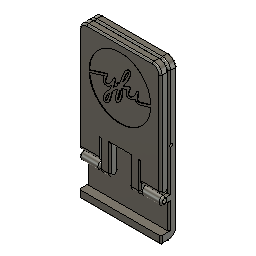
YFU Klap-Handy-Ständer (Autodesk Fusion 360 design; units mm, degrees)
Autodesk Fusion 360 part; units mm, degrees
sketch "Skizze1" plane through (0, 0, 0) normal (0, 0, 1) x (1, 0, 0)
  line L0 (25, -50) -> (-25, -50) construction
  line L1 (-25, -50) -> (-25, 45)
  line L2 (-20, 50) -> (20, 50)
  line L3 (25, 45) -> (25, -50)
  line L4 (25, -50) -> (-25, 50) construction
  line L5 (-25, -50) -> (25, 50) construction
  arc A0 (-20, 50) -> (-25, 45) centre (-20, 45) ccw
  arc A1 (25, 45) -> (20, 50) centre (20, 45) ccw
  line L6 (25, -45) -> (-25, -45)
  line L7 (25, -25) -> (-25, -25)
  line L8 (25, -20) -> (-25, -20)
  line L9 (-25, 50) -> (25, 0) construction
  line L10 (12.5, 7.5) -> (-12.5, 7.5) construction
  line L11 (-12.5, 7.5) -> (-12.5, 40.5)
  line L12 (-10.5, 42.5) -> (10.5, 42.5)
  line L13 (12.5, 40.5) -> (12.5, 7.5)
  line L14 (12.5, 7.5) -> (-12.5, 42.5) construction
  line L15 (-12.5, 7.5) -> (12.5, 42.5) construction
  line L16 (-12.5, 32.5) -> (12.5, 32.5)
  line L17 (-25, -20) -> (25, -25) construction
  line L18 (12.5, -25) -> (-12.5, -25)
  line L19 (-12.5, -25) -> (-12.5, -20)
  line L20 (-12.5, -20) -> (12.5, -20)
  line L21 (12.5, -20) -> (12.5, -25)
  line L22 (12.5, -25) -> (-12.5, -20) construction
  line L23 (-12.5, -25) -> (12.5, -20) construction
  arc A2 (-10.5, 42.5) -> (-12.5, 40.5) centre (-10.5, 40.5) ccw
  arc A3 (12.5, 40.5) -> (10.5, 42.5) centre (10.5, 40.5) ccw
  line L24 (25, -40) -> (-25, -40)
  line L25 (12.5, 7.5) -> (-12.5, 7.5) construction
  line L26 (-12.5, 7.5) -> (-12.5, 2.5)
  line L27 (-12.5, 2.5) -> (12.5, 2.5)
  line L28 (12.5, 2.5) -> (12.5, 7.5)
  point P0 (0, 25)
  point P1 (0, -22.5)
  dimension "d1" = 50
  dimension "d2" = 100
  dimension "d3" = 5
  dimension "d4" = 5
  dimension "d5" = 25
  dimension "d6" = 5
  dimension "d7" = 25
  dimension "d8" = 35
  dimension "d20" = 25
  dimension "d21" = 5
  dimension "d48" = 2
  dimension "d104" = 5
  dimension "d107" = 25
  dimension "d108" = 5
  constraint horizontal L0
  constraint perpendicular L0 L1
  constraint parallel L0 L2
  constraint parallel L1 L3
  constraint coincident L4 origin
  constraint coincident L5 origin
  constraint coincident L4.end L1
  constraint coincident L4.end L2
  constraint tangent L1 A0
  constraint tangent L2 A0
  constraint coincident L5.end L2
  constraint coincident L5.end L3
  constraint tangent L2 A1
  constraint tangent L3 A1
  constraint equal A0 A1
  constraint coincident L3 L9.end
  constraint horizontal L10
  constraint perpendicular L10 L11
  constraint parallel L10 L12
  constraint parallel L11 L13
  constraint coincident L14 P0
  constraint coincident L15 P0
  constraint midpoint L9 P0
  constraint horizontal L18
  constraint perpendicular L18 L19
  constraint parallel L18 L20
  constraint parallel L19 L21
  constraint coincident L22 P1
  constraint coincident L23 P1
  constraint midpoint L17 P1
  constraint coincident L14.end L11
  constraint coincident L14.end L12
  constraint tangent L11 A2
  constraint tangent L12 A2
  constraint coincident L15.end L12
  constraint coincident L15.end L13
  constraint tangent L12 A3
  constraint tangent L13 A3
  constraint equal A2 A3
  constraint horizontal L25
  constraint vertical L26
  constraint horizontal L27
  constraint vertical L28
  measures "d1" distance of L4.end L5.end
  measures "d2" distance of L0.end L4.end
  measures "d3" radius of A0
  measures "d7" distance of L14.end L15.end
  measures "d8" distance of L10.end L14.end
  measures "d20" distance of L19.end L20.end
  measures "d21" distance of L18.end L19.end
  measures "d48" radius of A2
  measures "d107" distance of L10.start L10.end
  measures "d108" distance of L10.start L27.end
extrude "Extrusion1" add sketch "Skizze1" along normal blind 5 makes body 1
extrude "Extrusion2" add sketch "Skizze1" along normal blind 10 contours L1 L3 L6 L24 | L1 L7 L8 L19 | L3 L7 L8 L21 bodies 1
extrude "Extrusion3" add sketch "Skizze1" along normal blind 2 contours L11 L12 L13 L16 A2 A3 bodies 1
fillet "Abrundung1" radius 5 1 edges at (0, -45, 0) on bodies 1
fillet "Abrundung2" radius 2.5 4 edges at (18.75, -25, 10) (-18.75, -25, 10) (18.75, -20, 10) (-18.75, -20, 10) on bodies 1
fillet "Abrundung3" radius 1 31 edges at (0, -45, 10) (25, -42.5, 10) (-25, -42.5, 10) (-25, 2.5, 0) (-23.5355, 48.5355, 0) (0, 50, 0) (23.5355, 48.5355, 0) (25, 2.5, 0) (25, -43.5355, 1.4645) (25, -45, 7.5) (-25, -43.5355, 1.4645) (-25, -45, 7.5) (25, -32.5, 5) (25, 12.5, 5) (23.5355, 48.5355, 5) (0, 50, 5) (-23.5355, 48.5355, 5) (-25, 12.5, 5) (25, -25, 6.25) (25, -22.5, 10) (25, -20, 6.25) (-25, -20, 6.25) (-25, -22.5, 10) (-25, -25, 6.25) (-25, -32.5, 5) (-12.5, -25, 6.25) (-12.5, -22.5, 10) (-12.5, -20, 6.25) (12.5, -20, 6.25) (12.5, -22.5, 10) (12.5, -25, 6.25) on bodies 1
sketch "Skizze2" plane through (25, 0, 0) normal (1, 0, 0) x (0, 0, -1)
  line L0 (-1, -40) -> (-1, 45)
  line L1 (-1, 45) -> (-4, 45)
  line L2 (-4, 45) -> (-4, -21)
  line L3 (-4, -21) -> (-7.5, -21)
  arc A0 (-7.5, -21) -> (-7.5, -24) centre (-7.5, -22.5) ccw
  line L4 (-7.5, -24) -> (-4, -24)
  line L5 (-4, -24) -> (-4, -40)
  line L6 (-9, -44) -> (-5, -44)
  line L7 (-9, -40) -> (-9, -44)
  arc A1 (-7.5, -20) -> (-7.5, -25) centre (-7.5, -22.5) ccw construction
  circle A2 centre (-7.5, -22.5) radius 1.35
  line L8 (-5, 7.5) -> (0, 7.5) construction
  line L9 (-5, 7.5) -> (-2, 7.5) construction
  line L10 (-2, 7.5) -> (-2, 12.5) construction
  line L11 (-2, 12.5) -> (-5, 12.5) construction
  line L12 (-5, 12.5) -> (-5, 7.5) construction
  line L13 (-5, 12.5) -> (-2, 7.5) construction
  circle A3 centre (-3.5, 10) radius 0.85
  line L14 (-4, -40) -> (-9, -40)
  arc A4 (-5, -44) -> (-1, -40) centre (-5, -40) ccw
  line L15 (0, 2.5) -> (-5, 2.5) construction
  line L16 (-5, 2.5) -> (-2, 2.5) construction
  line L17 (-2, 2.5) -> (-2, 7.5) construction
  line L18 (-2, 7.5) -> (-5, 7.5) construction
  line L19 (-5, 7.5) -> (-5, 2.5) construction
  line L20 (-5, 7.5) -> (-2, 2.5) construction
  circle A5 centre (-3.5, 5) radius 0.85
  arc A6 (-7.5, -20) -> (-7.5, -25) centre (-7.5, -22.5) ccw
  dimension "d24" = 2.7
  dimension "d25" = 3
  dimension "d26" = 5
  dimension "d27" = 1.7
  dimension "d109" = 3
  dimension "d110" = 5
  dimension "d111" = 1.7
  constraint horizontal L9
  constraint vertical L10
  constraint horizontal L11
  constraint vertical L12
  constraint coincident L8.start L9.start
  constraint midpoint L13 A3.centre
  constraint horizontal L16
  constraint vertical L17
  constraint horizontal L18
  constraint vertical L19
  constraint coincident L15.end L16.start
  constraint midpoint L20 A5.centre
  measures "d24" diameter of A2
  measures "d25" distance of L8.start L9.end
  measures "d26" distance of L8.start L11.end
  measures "d27" diameter of A3
  measures "d109" distance of L15.end L16.end
  measures "d110" distance of L15.end L8.start
  measures "d111" diameter of A5
extrude "Extrusion4" cut sketch "Skizze2" against normal blind 50 contours L2 A5 | L2 A5 | A2 bodies 1
chamfer "Fase2" distance 1.5 angle 45 1 edges at (0, 2.5, 5) on bodies 1
fillet "Abrundung13" radius 0.7 6 edges at (-12.5, 20.75, 5) (-11.9142, 41.9142, 5) (0, 42.5, 5) (11.9142, 41.9142, 5) (12.5, 20.75, 5) (0, 1, 5) on bodies 1
sketch "Skizze11" plane through (0, 0, 0) normal (0, 0, -1) x (-1, 0, 0)
  line L0 (24, -40) -> (24, 45)
  arc A0 (24, 45) -> (20, 49) centre (20, 45) ccw
  line L1 (20, 49) -> (-20, 49)
  arc A1 (-20, 49) -> (-24, 45) centre (-20, 45) ccw
  line L2 (-24, 45) -> (-24, -40)
  circle A2 centre (0, 20) radius 15
  line L3 (-24, -40) -> (24, -40)
  line L4 (12.5, 32.5) -> (12.5, 2.5)
  line L5 (12.5, 2.5) -> (-12.5, 2.5)
  line L6 (-12.5, 2.5) -> (-12.5, 32.5)
  line L7 (-12.5, 32.5) -> (12.5, 32.5)
extrude "Extrusion12" cut sketch "Skizze11" against normal blind 2 contours A2 L7 bodies 1
fillet "Abrundung14" radius 5 2 edges at (8.2916, 32.5, 1) (-8.2916, 32.5, 1) on bodies 1
fillet "Abrundung15" radius 1 5 edges at (-11.0912, 32.5, 2) (-8.4325, 32.6588, 2) (0, 35, 2) (8.4325, 32.6588, 2) (11.0912, 32.5, 2) on bodies 1
ref_plane "Arbeitsebene1" through (0, 15, 5.1) normal (0, 0, 1) x (1, 0, 0)
sketch "Skizze4" plane through (0, 0, 5.1) normal (0, 0, 1) x (1, 0, 0)
  line L0 (25, -25) -> (-25, -25) construction
  line L1 (-20, 50) -> (20, 50)
  line L2 (25, 45) -> (25, -25)
  line L3 (25, -25) -> (-25, -25)
  line L4 (-25, -25) -> (-25, 45)
  line L5 (-12.5, -25) -> (-12.5, -20) construction
  line L6 (12.5, -20) -> (12.5, -25) construction
  line L7 (-12.3, -25) -> (-12.3, -20) construction
  line L8 (12.3, -20) -> (12.3, -25) construction
  line L9 (25, -19) -> (-25, -19)
  line L10 (-12.3, -25) -> (12.5, -25)
  line L11 (12.5, -25) -> (12.5, -19)
  line L12 (12.5, -19) -> (-12.3, -19)
  line L13 (-12.3, -19) -> (-12.3, -25)
  arc A0 (-20, 50) -> (-25, 45) centre (-20, 45) ccw
  arc A1 (25, 45) -> (20, 50) centre (20, 45) ccw
  line L14 (6, -31.5) -> (-6, -31.5)
  line L15 (-6, -31.5) -> (-6, -6.5)
  line L16 (-6, -6.5) -> (6, -6.5)
  line L17 (6, -6.5) -> (6, -31.5)
  line L18 (6, -31.5) -> (-6, -6.5) construction
  line L19 (-6, -31.5) -> (6, -6.5) construction
  line L20 (12.5, -19) -> (12.5, -9)
  line L21 (-12.5, -25) -> (-12.3, -25)
  line L22 (-12.3, -25) -> (-12.3, -6)
  line L23 (-12.3, -6) -> (-12.5, -6)
  line L24 (-12.5, -6) -> (-12.5, -25)
  line L25 (12.5, -25) -> (12.3, -25)
  line L26 (12.3, -25) -> (12.3, -6)
  line L27 (12.3, -6) -> (12.5, -6)
  line L28 (12.5, -6) -> (12.5, -25)
  point P0 (25, 50)
  point P1 (-25, 50)
  point P2 (0, -19)
  dimension "d31" = 0.2
  dimension "d32" = 0.2
  dimension "d33" = 6
  dimension "d34" = 5
  dimension "d35" = 12
  dimension "d36" = 25
  dimension "d83" = 10
  dimension "d84" = 0.2
  dimension "d85" = 19
  dimension "d86" = 0.2
  dimension "d87" = 19
  constraint horizontal L1
  constraint vertical L2
  constraint horizontal L3
  constraint vertical L4
  constraint coincident L0.start L2.end
  constraint horizontal L10
  constraint vertical L11
  constraint horizontal L12
  constraint vertical L13
  constraint coincident L9 L11.end
  constraint tangent L4 A0
  constraint tangent L1 A0
  constraint tangent L1 A1
  constraint tangent L2 A1
  constraint equal A0 A1
  constraint horizontal L14
  constraint perpendicular L14 L15
  constraint parallel L14 L16
  constraint parallel L15 L17
  constraint coincident L18 P2
  constraint coincident L19 P2
  constraint midpoint L9 P2
  constraint perpendicular L12 L20
  constraint horizontal L21
  constraint vertical L22
  constraint horizontal L23
  constraint vertical L24
  constraint coincident L5.start L21.start
  constraint horizontal L25
  constraint vertical L26
  constraint horizontal L27
  constraint vertical L28
  constraint coincident L6.end L10.end
  measures "d34" radius of A0
  measures "d35" distance of L15.end L16.end
  measures "d36" distance of L14.end L15.end
  measures "d83" distance of L11.end L20.end
  measures "d84" distance of L5.start L7.start
  measures "d85" distance of L5.start L23.end
  measures "d86" distance of L6.end L8.end
  measures "d87" distance of L6.end L27.end
extrude "Extrusion5" add sketch "Skizze4" along normal blind 5 separate body contours L1 L2 L4 L9 L12 A0 A1 L15 L16 L17 L20 L22 L23 L24 L26 L27 L28 | L3 L9 L10 L12 L13 L15 L22 | L3 L9 L10 L12 L17 L26 makes body 2
fillet "Abrundung4" radius 2.5 8 edges at (-9.15, -25, 10.1) (9.15, -25, 10.1) (-9.15, -25, 5.1) (9.15, -25, 5.1) (-18.75, -19, 10.1) (-18.75, -19, 5.1) (18.75, -19, 10.1) (18.75, -19, 5.1) on bodies 2
sketch "Skizze5" plane through (-12.3, 0, 0) normal (-1, 0, 0) x (0, 0, 1)
  arc A0 (5.1, -22.5) -> (10.1, -22.5) centre (7.6, -22.5) ccw
  line L0 (10.1, -22.5) -> (10.1, -6)
  line L1 (5.1, -6) -> (5.1, -22.5)
  circle A1 centre (7.5, -22.5) radius 1.35 construction
  line L2 (10.1, -6) -> (5.1, -6)
  circle A2 centre (7.5, -22.5) radius 1.25
  dimension "d88" = 2.5
  constraint concentric A1 A2
  measures "d88" diameter of A2
extrude "Extrusion6" add sketch "Skizze5" along normal blind 2.5 contours A2 bodies 2
fillet "Abrundung11" radius 1 1 edges at (-14.8, -22.952, 6.3346) on bodies 2
sketch "Skizze10" plane through (12.3, 0, 0) normal (1, 0, 0) x (0, 0, -1)
  arc A0 (-10.1, -22.5) -> (-5.1, -22.5) centre (-7.6, -22.5) ccw
  line L0 (-5.1, -22.5) -> (-5.1, -6)
  line L1 (-5.1, -6) -> (-10.1, -6)
  line L2 (-10.1, -6) -> (-10.1, -22.5)
  circle A1 centre (-7.5, -22.5) radius 1.25
extrude "Extrusion11" add sketch "Skizze10" along normal blind 2.5 contours A1 bodies 2
fillet "Abrundung12" radius 1 1 edges at (14.8, -22.952, 8.6654) on bodies 2
fillet "Abrundung5" radius 1 12 edges at (0, 50, 10.1) (-23.5355, 48.5355, 10.1) (-25, 14.25, 10.1) (-25, -19, 7.6) (-25, 14.25, 5.1) (-23.5355, 48.5355, 5.1) (0, 50, 5.1) (23.5355, 48.5355, 5.1) (25, 14.25, 5.1) (25, -19, 7.6) (25, 14.25, 10.1) (23.5355, 48.5355, 10.1) on bodies 2
fillet "Abrundung6" radius 1 14 edges at (-6, -14.5, 5.1) (-6, -25, 7.6) (-6, -14.5, 10.1) (6, -14.5, 10.1) (6, -25, 7.6) (6, -14.5, 5.1) (-12.3, -14.25, 10.1) (-12.3, -25, 7.6) (-12.3, -14.25, 5.1) (0, -6.5, 10.1) (0, -6.5, 5.1) (12.3, -14.25, 10.1) (12.3, -25, 7.6) (12.3, -14.25, 5.1) on bodies 2
sketch "Skizze12" plane through (0, 0, 10.1) normal (0, 0, 1) x (1, 0, 0)
  line L0 (11.3, -6) -> (12.5, -6)
  line L1 (12.5, -6) -> (12.5, -16.5)
  line L2 (12.5, -16.5) -> (24, -16.5)
  line L3 (24, -16.5) -> (24, 45)
  arc A0 (24, 45) -> (20, 49) centre (20, 45) ccw
  line L4 (20, 49) -> (-20, 49)
  arc A1 (-20, 49) -> (-24, 45) centre (-20, 45) ccw
  line L5 (-24, 45) -> (-24, -16.5)
  line L6 (-24, -16.5) -> (-12.5, -16.5)
  line L7 (-12.5, -16.5) -> (-12.5, -6)
  line L8 (-12.5, -6) -> (-11.3, -6)
  line L9 (-11.3, -6) -> (-11.3, -22.5)
  line L10 (-11.3, -22.5) -> (-7, -22.5)
  line L11 (-7, -22.5) -> (-7, -5.5)
  line L12 (-7, -5.5) -> (7, -5.5)
  line L13 (7, -5.5) -> (7, -22.5)
  line L14 (7, -22.5) -> (11.3, -22.5)
  line L15 (11.3, -22.5) -> (11.3, -6)
  spline S0 degree 3 poles (-2.6838, 7.5631) (-6.7695, 8.189) (-10.2906, 9.9884) (-13.2686, 12.9724) knots 0 0 0 0 1 1 1 1
  spline S1 degree 3 poles (-13.2686, 12.9724) (-16.1569, 15.8667) (-17.8327, 19.1266) (-18.5618, 23.2694) knots 0 0 0 0 1 1 1 1
  spline S2 degree 3 poles (-18.5618, 23.2694) (-18.8031, 24.6407) (-18.7822, 25.0534) (-18.4646, 25.1911) knots 0 0 0 0 1 1 1 1
  spline S3 degree 3 poles (-18.4646, 25.1911) (-17.8092, 25.475) (-9.76, 27.9798) (-9.674, 27.9265) knots 0 0 0 0 1 1 1 1
  spline S4 degree 3 poles (-9.674, 27.9265) (-9.6207, 27.8936) (-9.7066, 27.4605) (-9.8648, 26.9642) knots 0 0 0 0 1 1 1 1
  spline S5 degree 3 poles (-9.8648, 26.9642) (-10.0932, 26.2478) (-10.1444, 25.8763) (-10.1131, 25.1616) knots 0 0 0 0 1 1 1 1
  spline S6 degree 3 poles (-10.1131, 25.1616) (-10.0766, 24.3254) (-10.047, 24.2344) (-9.6973, 23.8839) knots 0 0 0 0 1 1 1 1
  spline S7 degree 3 poles (-9.6973, 23.8839) (-9.352, 23.538) (-9.2491, 23.5031) (-8.4581, 23.463) knots 0 0 0 0 1 1 1 1
  spline S8 degree 3 poles (-8.4581, 23.463) (-7.7297, 23.4261) (-7.4993, 23.4642) (-6.9777, 23.7047) knots 0 0 0 0 1 1 1 1
  spline S9 degree 3 poles (-6.9777, 23.7047) (-6.6379, 23.8617) (-6.1264, 24.1866) (-5.8412, 24.4269) knots 0 0 0 0 1 1 1 1
  spline S10 degree 3 poles (-5.8412, 24.4269) (-5.5427, 24.6784) (-5.3038, 24.8071) (-5.2783, 24.7303) knots 0 0 0 0 1 1 1 1
  spline S11 degree 3 poles (-5.2783, 24.7303) (-5.2538, 24.6568) (-5.3283, 24.2458) (-5.4437, 23.8168) knots 0 0 0 0 1 1 1 1
  spline S12 degree 3 poles (-5.4437, 23.8168) (-5.6326, 23.1147) (-5.7468, 22.9379) (-6.5873, 22.0477) knots 0 0 0 0 1 1 1 1
  spline S13 degree 3 poles (-6.5873, 22.0477) (-8.9118, 19.5856) (-10.134, 17.4491) (-10.1331, 15.8494) knots 0 0 0 0 1 1 1 1
  spline S14 degree 3 poles (-10.1331, 15.8494) (-10.1324, 14.6369) (-9.4884, 14.0027) (-8.4325, 14.1744) knots 0 0 0 0 1 1 1 1
  spline S15 degree 3 poles (-8.4325, 14.1744) (-7.0063, 14.4063) (-6.242, 15.764) (-5.2511, 19.826) knots 0 0 0 0 1 1 1 1
  line L16 (-5.2511, 19.826) -> (-4.6667, 22.2223)
  line L17 (-4.6667, 22.2223) -> (-3.9246, 22.9298)
  spline S16 degree 3 poles (-3.9246, 22.9298) (-2.7402, 24.059) (-1.5395, 25.0022) (-1.4329, 24.887) knots 0 0 0 0 1 1 1 1
  spline S17 degree 3 poles (-1.4329, 24.887) (-1.3795, 24.8292) (-1.514, 24.1799) (-1.7318, 23.444) knots 0 0 0 0 1 1 1 1
  spline S18 degree 3 poles (-1.7318, 23.444) (-2.7517, 19.9986) (-2.8424, 18.0671) (-1.9967, 17.7982) knots 0 0 0 0 1 1 1 1
  spline S19 degree 3 poles (-1.9967, 17.7982) (-0.93, 17.4589) (0.3273, 18.9912) (1.0808, 21.5488) knots 0 0 0 0 1 1 1 1
  spline S20 degree 3 poles (1.0808, 21.5488) (1.4776, 22.8957) (1.5778, 24.7326) (1.3047, 25.6546) knots 0 0 0 0 1 1 1 1
  spline S21 degree 3 poles (1.3047, 25.6546) (0.9769, 26.761) (0.9481, 26.7111) (2.0568, 26.9523) knots 0 0 0 0 1 1 1 1
  spline S22 degree 3 poles (2.0568, 26.9523) (2.5987, 27.0703) (3.2944, 27.2507) (3.6028, 27.3533) knots 0 0 0 0 1 1 1 1
  spline S23 degree 3 poles (3.6028, 27.3533) (3.9112, 27.4559) (4.1935, 27.5098) (4.2302, 27.4731) knots 0 0 0 0 1 1 1 1
  spline S24 degree 3 poles (4.2302, 27.4731) (4.2669, 27.4363) (4.2112, 27.1003) (4.1065, 26.7264) knots 0 0 0 0 1 1 1 1
  spline S25 degree 3 poles (4.1065, 26.7264) (3.7103, 25.3114) (3.9314, 24.2356) (4.7289, 23.6984) knots 0 0 0 0 1 1 1 1
  spline S26 degree 3 poles (4.7289, 23.6984) (5.088, 23.4566) (5.2436, 23.4293) (6.0643, 23.4646) knots 0 0 0 0 1 1 1 1
  spline S27 degree 3 poles (6.0643, 23.4646) (7.1832, 23.5126) (7.8183, 23.7883) (8.7263, 24.6199) knots 0 0 0 0 1 1 1 1
  spline S28 degree 3 poles (8.7263, 24.6199) (9.0682, 24.933) (9.3778, 25.1892) (9.4143, 25.1892) knots 0 0 0 0 1 1 1 1
  spline S29 degree 3 poles (9.4143, 25.1892) (9.4508, 25.1892) (9.538, 24.9756) (9.6082, 24.7145) knots 0 0 0 0 1 1 1 1
  spline S30 degree 3 poles (9.6082, 24.7145) (9.6784, 24.4533) (9.9089, 24.0505) (10.1204, 23.8192) knots 0 0 0 0 1 1 1 1
  spline S31 degree 3 poles (10.1204, 23.8192) (10.4726, 23.4341) (10.5673, 23.3951) (11.2455, 23.3559) knots 0 0 0 0 1 1 1 1
  spline S32 degree 3 poles (11.2455, 23.3559) (12.0708, 23.3082) (13.4673, 23.6517) (16.8937, 24.7454) knots 0 0 0 0 1 1 1 1
  spline S33 degree 3 poles (16.8937, 24.7454) (18.0404, 25.1115) (18.8214, 25.3056) (18.8818, 25.2396) knots 0 0 0 0 1 1 1 1
  spline S34 degree 3 poles (18.8818, 25.2396) (19.0252, 25.0827) (18.816, 23.3477) (18.4868, 21.9631) knots 0 0 0 0 1 1 1 1
  spline S35 degree 3 poles (18.4868, 21.9631) (17.6453, 18.4243) (16.0609, 15.5996) (13.4401, 12.9653) knots 0 0 0 0 1 1 1 1
  spline S36 degree 3 poles (13.4401, 12.9653) (10.7097, 10.2211) (7.6318, 8.546) (3.8206, 7.7302) knots 0 0 0 0 1 1 1 1
  spline S37 degree 3 poles (3.8206, 7.7302) (2.3283, 7.4107) (-1.1121, 7.3224) (-2.6838, 7.5631) knots 0 0 0 0 1 1 1 1
  spline S38 degree 3 poles (-8.9324, 15.5954) (-9.1427, 16.1447) (-8.3658, 17.9357) (-7.3226, 19.3064) knots 0 0 0 0 1 1 1 1
  spline S39 degree 3 poles (-7.3226, 19.3064) (-6.2882, 20.6655) (-6.2237, 20.5061) (-6.9022, 18.2682) knots 0 0 0 0 1 1 1 1
  spline S40 degree 3 poles (-6.9022, 18.2682) (-7.2852, 17.0047) (-7.7008, 16.0881) (-8.0765, 15.6776) knots 0 0 0 0 1 1 1 1
  spline S41 degree 3 poles (-8.0765, 15.6776) (-8.3517, 15.377) (-8.831, 15.3309) (-8.9324, 15.5954) knots 0 0 0 0 1 1 1 1
  spline S42 degree 3 poles (-1.3332, 19.5512) (-1.481, 19.6993) (-0.325, 24.3766) (-0.025, 24.8442) knots 0 0 0 0 1 1 1 1
  spline S43 degree 3 poles (-0.025, 24.8442) (0.0708, 24.9935) (0.0987, 24.9929) (0.1988, 24.8402) knots 0 0 0 0 1 1 1 1
  spline S44 degree 3 poles (0.1988, 24.8402) (0.5604, 24.2882) (0.048, 21.7491) (-0.7463, 20.1571) knots 0 0 0 0 1 1 1 1
  spline S45 degree 3 poles (-0.7463, 20.1571) (-1.0602, 19.528) (-1.1832, 19.4009) (-1.3332, 19.5512) knots 0 0 0 0 1 1 1 1
  spline S46 degree 3 poles (10.9327, 24.733) (10.6107, 25.0895) (10.6557, 26.3412) (11.0464, 27.8973) knots 0 0 0 0 1 1 1 1
  spline S47 degree 3 poles (11.0464, 27.8973) (11.3884, 29.2597) (11.3679, 29.5717) (10.9286, 29.6822) knots 0 0 0 0 1 1 1 1
  spline S48 degree 3 poles (10.9286, 29.6822) (10.5307, 29.7823) (10.262, 29.5049) (9.9518, 28.6737) knots 0 0 0 0 1 1 1 1
  spline S49 degree 3 poles (9.9518, 28.6737) (9.1055, 26.4062) (7.3284, 24.6118) (5.9257, 24.6086) knots 0 0 0 0 1 1 1 1
  spline S50 degree 3 poles (5.9257, 24.6086) (5.3679, 24.6073) (5.0773, 24.8977) (5.0773, 25.4564) knots 0 0 0 0 1 1 1 1
  spline S51 degree 3 poles (5.0773, 25.4564) (5.0773, 25.889) (5.567, 27.3425) (6.0071, 28.216) knots 0 0 0 0 1 1 1 1
  spline S52 degree 3 poles (6.0071, 28.216) (6.4412, 29.0778) (6.4558, 29.4529) (6.0623, 29.6326) knots 0 0 0 0 1 1 1 1
  spline S53 degree 3 poles (6.0623, 29.6326) (5.8053, 29.7499) (5.6475, 29.7015) (4.756, 29.2322) knots 0 0 0 0 1 1 1 1
  spline S54 degree 3 poles (4.756, 29.2322) (3.589, 28.6179) (2.3027, 28.1557) (2.1595, 28.2991) knots 0 0 0 0 1 1 1 1
  spline S55 degree 3 poles (2.1595, 28.2991) (2.1055, 28.3532) (2.4038, 28.8668) (2.8222, 29.4403) knots 0 0 0 0 1 1 1 1
  spline S56 degree 3 poles (2.8222, 29.4403) (4.2856, 31.4459) (5.6548, 33.9063) (6.1799, 35.4738) knots 0 0 0 0 1 1 1 1
  spline S57 degree 3 poles (6.1799, 35.4738) (6.6534, 36.8872) (6.5416, 37.7007) (5.8274, 38.0403) knots 0 0 0 0 1 1 1 1
  spline S58 degree 3 poles (5.8274, 38.0403) (5.0716, 38.3997) (4.4513, 38.185) (3.6427, 37.2838) knots 0 0 0 0 1 1 1 1
  spline S59 degree 3 poles (3.6427, 37.2838) (2.8825, 36.4366) (2.1505, 34.868) (0.9577, 31.5303) knots 0 0 0 0 1 1 1 1
  spline S60 degree 3 poles (0.9577, 31.5303) (0.4089, 29.9945) (-0.098, 28.5911) (-0.1687, 28.4117) knots 0 0 0 0 1 1 1 1
  spline S61 degree 3 poles (-0.1687, 28.4117) (-0.2927, 28.097) (-0.3188, 28.0881) (-0.9, 28.1608) knots 0 0 0 0 1 1 1 1
  spline S62 degree 3 poles (-0.9, 28.1608) (-1.3783, 28.2208) (-1.5425, 28.1963) (-1.6961, 28.0425) knots 0 0 0 0 1 1 1 1
  spline S63 degree 3 poles (-1.6961, 28.0425) (-1.9871, 27.7508) (-1.9304, 27.4489) (-1.5249, 27.1308) knots 0 0 0 0 1 1 1 1
  line L18 (-1.5249, 27.1308) -> (-1.1603, 26.8449)
  line L19 (-1.1603, 26.8449) -> (-1.4378, 26.6117)
  spline S64 degree 3 poles (-1.4378, 26.6117) (-2.4284, 25.7796) (-3.6546, 24.8401) (-3.7503, 24.8401) knots 0 0 0 0 1 1 1 1
  spline S65 degree 3 poles (-3.7503, 24.8401) (-3.9116, 24.8401) (-3.9168, 24.8133) (-3.3268, 27.0147) knots 0 0 0 0 1 1 1 1
  spline S66 degree 3 poles (-3.3268, 27.0147) (-2.7479, 29.1746) (-2.7338, 29.5556) (-3.228, 29.6799) knots 0 0 0 0 1 1 1 1
  spline S67 degree 3 poles (-3.228, 29.6799) (-3.6375, 29.7829) (-3.7922, 29.6128) (-4.4451, 28.3423) knots 0 0 0 0 1 1 1 1
  spline S68 degree 3 poles (-4.4451, 28.3423) (-5.567, 26.1595) (-6.9344, 24.768) (-8.0854, 24.638) knots 0 0 0 0 1 1 1 1
  spline S69 degree 3 poles (-8.0854, 24.638) (-8.4275, 24.5994) (-8.6857, 24.6302) (-8.7972, 24.723) knots 0 0 0 0 1 1 1 1
  spline S70 degree 3 poles (-8.7972, 24.723) (-9.1952, 25.0539) (-8.862, 26.5789) (-8.029, 28.2401) knots 0 0 0 0 1 1 1 1
  spline S71 degree 3 poles (-8.029, 28.2401) (-7.6154, 29.0647) (-7.5983, 29.455) (-7.9683, 29.6239) knots 0 0 0 0 1 1 1 1
  spline S72 degree 3 poles (-7.9683, 29.6239) (-8.1976, 29.7286) (-9.0143, 29.5023) (-13.0482, 28.2168) knots 0 0 0 0 1 1 1 1
  spline S73 degree 3 poles (-13.0482, 28.2168) (-15.692, 27.3744) (-18.0296, 26.6308) (-18.2431, 26.5645) knots 0 0 0 0 1 1 1 1
  spline S74 degree 3 poles (-18.2431, 26.5645) (-18.839, 26.3794) (-18.8777, 26.4952) (-18.7281, 28.0176) knots 0 0 0 0 1 1 1 1
  spline S75 degree 3 poles (-18.7281, 28.0176) (-18.2581, 32.7986) (-16.3742, 36.6827) (-12.9045, 40.0239) knots 0 0 0 0 1 1 1 1
  spline S76 degree 3 poles (-12.9045, 40.0239) (-10.0959, 42.7285) (-6.7747, 44.3859) (-2.8764, 45.0283) knots 0 0 0 0 1 1 1 1
  spline S77 degree 3 poles (-2.8764, 45.0283) (-1.3312, 45.283) (1.7107, 45.2571) (3.3556, 44.9753) knots 0 0 0 0 1 1 1 1
  spline S78 degree 3 poles (3.3556, 44.9753) (11.151, 43.6399) (17.4343, 37.3283) (18.7094, 29.5524) knots 0 0 0 0 1 1 1 1
  spline S79 degree 3 poles (18.7094, 29.5524) (18.9977, 27.7937) (19.0516, 26.8801) (18.8753, 26.7366) knots 0 0 0 0 1 1 1 1
  spline S80 degree 3 poles (18.8753, 26.7366) (18.5025, 26.4332) (12.0358, 24.4924) (11.3944, 24.4915) knots 0 0 0 0 1 1 1 1
  spline S81 degree 3 poles (11.3944, 24.4915) (11.2607, 24.4915) (11.0529, 24.6) (10.9327, 24.733) knots 0 0 0 0 1 1 1 1
  spline S82 degree 3 poles (2.0022, 30.8031) (2.1544, 31.3306) (3.1246, 33.9346) (3.4109, 34.5845) knots 0 0 0 0 1 1 1 1
  spline S83 degree 3 poles (3.4109, 34.5845) (3.7866, 35.4368) (4.6722, 36.7775) (4.9234, 36.8741) knots 0 0 0 0 1 1 1 1
  spline S84 degree 3 poles (4.9234, 36.8741) (5.0294, 36.9149) (5.1659, 36.8984) (5.2266, 36.8375) knots 0 0 0 0 1 1 1 1
  spline S85 degree 3 poles (5.2266, 36.8375) (5.5107, 36.5529) (4.203, 33.683) (2.8667, 31.6581) knots 0 0 0 0 1 1 1 1
  spline S86 degree 3 poles (2.8667, 31.6581) (2.1479, 30.569) (1.8494, 30.2737) (2.0022, 30.8031) knots 0 0 0 0 1 1 1 1
extrude "Extrusion13" cut sketch "Skizze12" against normal blind 0.4 contours S0 S1 S2 S3 S4 S5 S6 S7 S8 S9 S10 S11 S12 S13 S14 S15 L16 L17 S16 S17 S18 S19 S20 S21 S22 S23 S24 S25 S26 S27 S28 S29 S30 S31 S32 S33 S34 S35 S36 S37 | S38 S39 S40 S41 | S42 S43 S44 S45 | S46 S47 S48 S49 S50 S51 S52 S53 S54 S55 S56 S57 S58 S59 S60 S61 S62 S63 L18 L19 S64 S65 S66 S67 S68 S69 S70 S71 S72 S73 S74 S75 S76 S77 S78 S79 S80 S81 | S82 S83 S84 S85 S86 bodies 2
ref_plane "Arbeitsebene2" through (0, 0, 2.1) normal (0, 0, 1) x (1, 0, 0)
sketch "Skizze6" plane through (0, 0, 2.1) normal (0, 0, 1) x (1, 0, 0)
  line L0 (-12.5, 7.5) -> (-12.5, 40.5) construction
  arc A0 (-10.5, 42.5) -> (-12.5, 40.5) centre (-10.5, 40.5) ccw construction
  line L1 (-10.5, 42.5) -> (10.5, 42.5) construction
  arc A1 (12.5, 40.5) -> (10.5, 42.5) centre (10.5, 40.5) ccw construction
  line L2 (12.5, 40.5) -> (12.5, 7.5) construction
  line L3 (12.5, 7.5) -> (-12.5, 7.5) construction
  line L4 (-12.3, 2.7) -> (-12.3, 40.5)
  arc A2 (-10.5, 42.3) -> (-12.3, 40.5) centre (-10.5, 40.5) ccw
  line L5 (-10.5, 42.3) -> (10.5, 42.3)
  arc A3 (12.3, 40.5) -> (10.5, 42.3) centre (10.5, 40.5) ccw
  line L6 (12.3, 40.5) -> (12.3, 2.7)
  line L7 (12.3, 7.7) -> (-12.3, 7.7)
  line L8 (8.5, -17.3) -> (-8.5, -17.3)
  line L9 (-8.5, -17.3) -> (-8.5, 32.7)
  line L10 (-8.5, 32.7) -> (8.5, 32.7)
  line L11 (8.5, 32.7) -> (8.5, -17.3)
  line L12 (8.5, -17.3) -> (-8.5, 32.7) construction
  line L13 (-8.5, -17.3) -> (8.5, 32.7) construction
  line L14 (-12.5, 2.5) -> (12.5, 2.5) construction
  line L15 (12.5, 2.5) -> (-12.5, 2.5) construction
  line L16 (12.5, 2.7) -> (-12.5, 2.7)
  line L17 (-10.5, 40.5) -> (-12.3, 40.5) construction
  line L18 (-12.3, 40.5) -> (-12.3, 42.3)
  line L19 (-12.3, 42.3) -> (-10.5, 42.3)
  line L20 (-10.5, 42.3) -> (-10.5, 40.5) construction
  line L21 (10.5, 40.5) -> (12.3, 40.5) construction
  line L22 (12.3, 40.5) -> (12.3, 42.3)
  line L23 (12.3, 42.3) -> (10.5, 42.3)
  line L24 (10.5, 42.3) -> (10.5, 40.5) construction
  point P0 (0, 7.7)
  dimension "d56" = 17
  dimension "d57" = 50
  dimension "d112" = 0.2
  dimension "d118" = 1.8
  dimension "d119" = 1.8
  dimension "d120" = 1.8
  dimension "d121" = 1.8
  constraint horizontal L8
  constraint perpendicular L8 L9
  constraint parallel L8 L10
  constraint parallel L9 L11
  constraint coincident L12 P0
  constraint coincident L13 P0
  constraint midpoint L7 P0
  constraint concentric A0 A2
  constraint concentric A1 A3
  constraint tangent L4 A2
  constraint tangent A2 L5
  constraint tangent A3 L6
  constraint tangent L5 A3
  constraint coincident L7.end L4
  constraint coincident L16 L4.start
  constraint coincident L7.start L6
  constraint coincident L16 L6.end
  constraint horizontal L17
  constraint vertical L18
  constraint horizontal L19
  constraint vertical L20
  constraint coincident A0.centre A2.centre
  constraint horizontal L21
  constraint vertical L22
  constraint horizontal L23
  constraint vertical L24
  constraint coincident A1.centre A3.centre
  measures "d56" distance of L9.end L10.end
  measures "d57" distance of L8.end L9.end
  measures "d118" distance of A0.centre L4.end
  measures "d119" distance of A0.centre A2.start
  measures "d120" distance of A1.centre A3.start
  measures "d121" distance of A1.centre L5.end
extrude "Extrusion7" add sketch "Skizze6" along normal blind 2.8 separate body contours L4 L7 L9 L16 | L4 A2 L5 A3 L6 L7 L9 L10 L11 | L6 L7 L11 L16 makes body 3
fillet "Abrundung7" radius 1.25 4 edges at (-10.4, 2.7, 2.1) (10.4, 2.7, 2.1) (10.4, 2.7, 4.9) (-10.4, 2.7, 4.9) on bodies 3
sketch "Skizze7" plane through (12.3, 0, 0) normal (1, 0, 0) x (0, 0, -1)
  arc A0 (-4, 9.3126) -> (-4, 10.6874) centre (-3.5, 10) ccw construction
  spline S0 degree 3 poles (-4, 9.3126) (-4.0261, 9.3316) (-4.0515, 9.3523) (-4.1338, 9.4281) (-4.1841, 9.4903) (-4.2617, 9.6156) (-4.2953, 9.6895) (-4.3395, 9.8443) (-4.35, 9.9252) (-4.35, 10.0748) (-4.3395, 10.1557) (-4.2953, 10.3105) (-4.2617, 10.3844) (-4.1841, 10.5097) (-4.1338, 10.5719) (-4.0515, 10.6477) (-4.0261, 10.6684) (-4, 10.6874) knots 0.157959 0.157959 0.157959 0.157959 0.167067 0.167067 0.18915 0.18915 0.211603 0.211603 0.234055 0.234055 0.256507 0.256507 0.278959 0.278959 0.301043 0.301043 0.310151 0.310151 0.310151 0.310151 construction
  circle A1 centre (-3.5, 10) radius 0.75
  circle A2 centre (-3.5, 5) radius 0.75
  line L0 (-2.1, 40.5) -> (-4.9, 40.5)
  arc A3 (-4.9, 3.95) -> (-3.65, 2.7) centre (-3.65, 3.95) ccw
  line L1 (-3.65, 2.7) -> (-3.35, 2.7)
  arc A4 (-3.35, 2.7) -> (-2.1, 3.95) centre (-3.35, 3.95) ccw
  line L2 (-2.1, 3.95) -> (-2.1, 40.5)
  line L3 (-4.9, 40.5) -> (-4.9, 3.95)
  dimension "d58" = 1.5
  dimension "d113" = 1.5
  constraint concentric A0 A1
  measures "d58" diameter of A1
  measures "d113" diameter of A2
extrude "Extrusion8" add sketch "Skizze7" along normal blind 2 contours A2 bodies 3
fillet "Abrundung9" radius 0.5 1 edges at (14.3, 4.7288, 4.1992) on bodies 3
sketch "Skizze8" plane through (-12.3, 0, 0) normal (-1, 0, 0) x (0, 0, 1)
  circle A0 centre (3.5, 10) radius 0.75
  circle A1 centre (3.5, 5) radius 0.75
  line L0 (4.9, 40.5) -> (2.1, 40.5)
  arc A2 (3.65, 2.7) -> (4.9, 3.95) centre (3.65, 3.95) ccw
  line L1 (4.9, 3.95) -> (4.9, 40.5)
  line L2 (2.1, 40.5) -> (2.1, 3.95)
  arc A3 (2.1, 3.95) -> (3.35, 2.7) centre (3.35, 3.95) ccw
  line L3 (3.35, 2.7) -> (3.65, 2.7)
extrude "Extrusion9" add sketch "Skizze8" along normal blind 2 contours A1 bodies 3
fillet "Abrundung10" radius 0.5 1 edges at (-14.3, 4.7288, 2.8008) on bodies 3
sketch "Skizze9" plane through (0, 0, 5.1) normal (0, 0, -1) x (-1, 0, 0)
  line L0 (12.5, -16.5) -> (24, -16.5)
  line L1 (24, -16.5) -> (24, 45)
  arc A0 (24, 45) -> (20, 49) centre (20, 45) ccw
  line L2 (20, 49) -> (-20, 49)
  arc A1 (-20, 49) -> (-24, 45) centre (-20, 45) ccw
  line L3 (-24, 45) -> (-24, -16.5)
  line L4 (-24, -16.5) -> (-12.5, -16.5)
  line L5 (-11.3, -22.5) -> (-7, -22.5)
  line L6 (-7, -22.5) -> (-7, -5.5)
  line L7 (-7, -5.5) -> (7, -5.5)
  line L8 (7, -5.5) -> (7, -22.5)
  line L9 (7, -22.5) -> (11.3, -22.5)
  line L10 (11.3, -22.5) -> (11.3, -6)
  line L11 (-10.5, 42.3) -> (10.5, 42.3) construction
  line L12 (-8.5, 7.7) -> (-12, 7.7) construction
  line L13 (12, 7.7) -> (8.5, 7.7) construction
  line L14 (-10.5, 42.3) -> (10.3, 42.3) construction
  line L15 (10.3, 42.3) -> (10.3, 7.7) construction
  line L16 (10.3, 7.7) -> (-10.5, 7.7) construction
  line L17 (-10.5, 7.7) -> (-10.5, 42.3) construction
  line L18 (11.8, 6.2) -> (-12, 6.2) construction
  line L19 (-12, 6.2) -> (-12, 43.8)
  line L20 (-12, 43.8) -> (11.8, 43.8) construction
  line L21 (11.8, 43.8) -> (11.8, 6.2)
  line L22 (-12, 31.8) -> (11.8, 31.8)
  line L23 (-12, 28.8) -> (11.8, 28.8)
  line L24 (-12, 25.3) -> (11.8, 25.3)
  line L25 (-12, 22.3) -> (11.8, 22.3)
  line L26 (-12, 18.8) -> (11.8, 18.8)
  line L27 (-12, 15.8) -> (11.8, 15.8)
  line L28 (-12, 12.3) -> (11.8, 12.3)
  line L29 (-12, 9.3) -> (11.8, 9.3)
  line L30 (-12, 5.8) -> (11.8, 5.8)
  line L31 (-12, 2.8) -> (11.8, 2.8)
  line L32 (-12, 5.8) -> (-12, 2.8)
  line L33 (11.8, 5.8) -> (11.8, 2.8)
  line L34 (11.3, -6) -> (12.5, -6)
  line L35 (12.5, -6) -> (12.5, -16.5)
  line L36 (-12.5, -16.5) -> (-12.5, -6)
  line L37 (-12.5, -6) -> (-11.3, -6)
  line L38 (-11.3, -6) -> (-11.3, -22.5)
  dimension "d67" = 20.8
  dimension "d68" = -1.5
  dimension "d69" = 12
  dimension "d70" = 3
  dimension "d71" = 3.5
  dimension "d72" = 3
  dimension "d73" = 3.5
  dimension "d74" = 3
  dimension "d75" = 3.5
  dimension "d76" = 3
  dimension "d80" = 3.5
  dimension "d82" = 3
  constraint horizontal L14
  constraint vertical L15
  constraint horizontal L16
  constraint vertical L17
  constraint coincident L13 L15.end
  constraint coincident L11.start L14.start
  constraint perpendicular L31 L32
  constraint perpendicular L31 L33
  measures "d67" distance of L11.start L14.end
extrude "Extrusion10" cut sketch "Skizze9" against normal blind 3 contours L19 L21 L28 L29 | L19 L21 L26 L27 | L19 L21 L24 L25 | L19 L21 L22 L23 | L30 L31 L32 L33 bodies 2
chamfer "Fase1" distance 1.5 angle 45 10 edges at (0.1, 31.8, 8.1) (0.1, 25.3, 8.1) (0.1, 18.8, 8.1) (0.1, 12.3, 8.1) (0.1, 28.8, 8.1) (0.1, 22.3, 8.1) (0.1, 15.8, 8.1) (0.1, 9.3, 8.1) (0.1, 2.8, 8.1) (0.1, 5.8, 8.1) tangent chain off on bodies 2
sketch "Skizze13" plane through (0, 0, 2.1) normal (0, 0, -1) x (-1, 0, 0)
  line L0 (-12.3, 3.95) -> (-8.5, 3.95)
  line L1 (-8.5, 3.95) -> (-8.5, 32.7)
  line L2 (-8.5, 32.7) -> (8.5, 32.7)
  line L3 (8.5, 32.7) -> (8.5, 3.95)
  line L4 (8.5, 3.95) -> (12.3, 3.95)
  arc A0 (-10.5, 42.3) -> (-12.3, 40.5) centre (-10.5, 40.5) ccw construction
  arc A1 (12.3, 40.5) -> (10.5, 42.3) centre (10.5, 40.5) ccw construction
  line L5 (-10.5, 40.5) -> (-12.3, 40.5)
  line L6 (-12.3, 40.5) -> (-12.3, 42.3)
  line L7 (-12.3, 42.3) -> (-10.5, 42.3)
  line L8 (-10.5, 42.3) -> (-10.5, 40.5)
  line L9 (10.5, 40.5) -> (12.3, 40.5)
  line L10 (12.3, 40.5) -> (12.3, 42.3)
  line L11 (12.3, 42.3) -> (10.5, 42.3)
  line L12 (10.5, 42.3) -> (10.5, 40.5)
  line L13 (12.3, 3.95) -> (12.3, 40.5)
  arc A2 (12.3, 40.5) -> (10.5, 42.3) centre (10.5, 40.5) ccw
  line L14 (10.5, 42.3) -> (-10.5, 42.3)
  arc A3 (-10.5, 42.3) -> (-12.3, 40.5) centre (-10.5, 40.5) ccw
  line L15 (-12.3, 40.5) -> (-12.3, 3.95)
  dimension "d124" = 1.8
  dimension "d125" = 1.8
  dimension "d126" = 1.8
  dimension "d127" = 1.8
  constraint horizontal L5
  constraint vertical L6
  constraint horizontal L7
  constraint vertical L8
  constraint horizontal L9
  constraint vertical L10
  constraint horizontal L11
  constraint vertical L12
  constraint coincident A1.centre L9.start
  measures "d124" distance of A0.centre A0.end
  measures "d125" distance of A0.centre A0.start
  measures "d126" distance of A1.centre A1.start
  measures "d127" distance of A1.centre A1.end
extrude "Extrusion14" cut sketch "Skizze13" against normal blind 2.8 contours L5 L8 A3 | L6 L7 A3 | L9 L12 A2 | L10 L11 A2 bodies 3
fillet "Abrundung17" radius 1 6 edges at (-10.5, 40.5, 3.5) (-12.3, 40.5, 3.5) (-10.5, 42.3, 3.5) (10.5, 42.3, 3.5) (12.3, 40.5, 3.5) (10.5, 40.5, 3.5) on bodies 3
fillet "Abrundung18" radius 0.5 24 edges at (12.3, 21.725, 4.9) (12.3, 3.0661, 4.5339) (12.3, 2.7, 3.5) (12.3, 3.0661, 2.4661) (12.3, 21.725, 2.1) (12.0401, 40.1725, 2.1) (10.7838, 40.7838, 2.1) (10.1725, 42.0401, 2.1) (-0.005, 42.3, 2.1) (-10.1808, 42.0416, 2.1) (-10.7929, 40.7929, 2.1) (-12.0416, 40.1808, 2.1) (-12.3, 21.73, 2.1) (-12.3, 3.0661, 2.4661) (-12.3, 2.7, 3.5) (-12.3, 3.0661, 4.5339) (-12.3, 21.73, 4.9) (-12.0416, 40.1808, 4.9) (-10.7929, 40.7929, 4.9) (-10.1808, 42.0416, 4.9) (-0.005, 42.3, 4.9) (10.1725, 42.0401, 4.9) (10.7838, 40.7838, 4.9) (12.0401, 40.1725, 4.9) on bodies 3
extrude "Extrusion17" add 1 faces at (-2.8333, 32.7, 3.9667) along direction (0, -1, 0) blind 15 on bodies 3 bodies 3
fillet "Abrundung20" radius 8 2 edges at (8.5, 17.7, 3.5) (-8.5, 17.7, 3.5) on bodies 3
sketch "Skizze16" plane through (0, 0, 4.9) normal (0, 0, 1) x (1, 0, 0)
  line L0 (-11.8, 39.51) -> (-11.8, 3.95)
  line L1 (-11.8, 3.95) -> (-8.5, 3.95)
  line L2 (-8.5, 3.95) -> (-8.5, 9.7)
  arc A0 (-0.5, 17.7) -> (-8.5, 9.7) centre (-0.5, 9.7) ccw
  line L3 (-0.5, 17.7) -> (0.5, 17.7)
  arc A1 (8.5, 9.7) -> (0.5, 17.7) centre (0.5, 9.7) ccw
  line L4 (8.5, 9.7) -> (8.5, 3.95)
  line L5 (8.5, 3.95) -> (11.8, 3.95)
  line L6 (11.8, 3.95) -> (11.8, 39.5)
  arc A2 (11.8, 39.5) -> (11.3477, 39.9977) centre (11.3, 39.5) ccw
  arc A3 (9.9977, 41.3477) -> (11.3477, 39.9977) centre (11.4909, 41.4909) ccw
  arc A4 (9.9977, 41.3477) -> (9.5, 41.8) centre (9.5, 41.3) ccw
  line L7 (9.5, 41.8) -> (-9.51, 41.8)
  arc A5 (-9.51, 41.8) -> (-10.0075, 41.35) centre (-9.51, 41.3) ccw
  arc A6 (-11.35, 40.0075) -> (-10.0075, 41.35) centre (-11.5, 41.5) ccw
  arc A7 (-11.35, 40.0075) -> (-11.8, 39.51) centre (-11.3, 39.51) ccw
  line L8 (-11.5, 41.5) -> (0, 17.7) construction
  line L9 (11.4909, 41.4909) -> (0, 17.7) construction
  line L10 (-5.75, 29.6) -> (5.7454, 29.5954) construction
  circle A8 centre (-0.0023, 29.5977) radius 6.5
  dimension "d144" = 13
  constraint coincident A6.centre L8.start
  constraint midpoint L3 L8.end
  constraint coincident A3.centre L9.start
  constraint midpoint L8 L10.start
  constraint midpoint L9 L10.end
  constraint midpoint L10 A8.centre
  measures "d144" diameter of A8
extrude "Extrusion18" cut sketch "Skizze16" against normal blind 2.8 contours A8 bodies 3
fillet "Abrundung19" radius 0.5 18 edges at (8.5, 6.825, 4.9) (8.5, 3.0661, 4.5339) (8.5, 2.7, 3.5) (8.5, 3.0661, 2.4661) (8.5, 6.825, 2.1) (6.1569, 15.3569, 2.1) (0, 17.7, 2.1) (-6.1569, 15.3569, 2.1) (-8.5, 6.825, 2.1) (-8.5, 3.0661, 2.4661) (-8.5, 2.7, 3.5) (-8.5, 3.0661, 4.5339) (-8.5, 6.825, 4.9) (-6.1569, 15.3569, 4.9) (0, 17.7, 4.9) (6.1569, 15.3569, 4.9) (-6.0624, 27.2472, 2.1) (-6.0624, 31.9482, 4.9) on bodies 3
sketch "Skizze14" plane through (25, 0, 0) normal (1, 0, 0) x (0, 0, -1)
  arc A0 (-4, 4.3126) -> (-4, 5.6874) centre (-3.5, 5) ccw
  line L0 (-4, 4.3126) -> (-4, -21)
  line L1 (-4, -21) -> (-7.5, -21)
  arc A1 (-7.5, -21) -> (-7.5, -24) centre (-7.5, -22.5) ccw
  line L2 (-7.5, -24) -> (-4, -24)
  line L3 (-4, -24) -> (-4, -40)
  line L4 (-4, -40) -> (-9, -40)
  line L5 (-9, -40) -> (-9, -44)
  line L6 (-9, -44) -> (-5, -44)
  arc A2 (-5, -44) -> (-1, -40) centre (-5, -40) ccw
  line L7 (-1, -40) -> (-1, 45)
  line L8 (-1, 45) -> (-4, 45)
  line L9 (-4, 45) -> (-4, 5.6874)
  circle A3 centre (-7.5, -22.5) radius 1.35
  circle A4 centre (-7.5, -22.5) radius 1.35
  arc A5 (-4, 4.3126) -> (-4, 5.6874) centre (-3.5, 5) ccw
  spline S0 degree 3 poles (-4, 4.3126) (-4.0261, 4.3316) (-4.0515, 4.3523) (-4.1338, 4.4281) (-4.1841, 4.4903) (-4.2617, 4.6156) (-4.2953, 4.6895) (-4.3395, 4.8443) (-4.35, 4.9252) (-4.35, 5.0748) (-4.3395, 5.1557) (-4.2953, 5.3105) (-4.2617, 5.3844) (-4.1841, 5.5097) (-4.1338, 5.5719) (-4.0515, 5.6477) (-4.0261, 5.6684) (-4, 5.6874) knots 0.157959 0.157959 0.157959 0.157959 0.167067 0.167067 0.18915 0.18915 0.211603 0.211603 0.234055 0.234055 0.256507 0.256507 0.278959 0.278959 0.301043 0.301043 0.310151 0.310151 0.310151 0.310151
extrude "Extrusion15" [suppressed]
sketch "Skizze15" plane through (-25, 0, 0) normal (-1, 0, 0) x (0, 0, 1)
  arc A0 (4, 5.6874) -> (4, 4.3126) centre (3.5, 5) ccw
  line L0 (4, 5.6874) -> (4, 45)
  line L1 (4, 45) -> (1, 45)
  line L2 (1, 45) -> (1, -40)
  arc A1 (1, -40) -> (5, -44) centre (5, -40) ccw
  line L3 (5, -44) -> (9, -44)
  line L4 (9, -44) -> (9, -40)
  line L5 (9, -40) -> (4, -40)
  line L6 (4, -40) -> (4, -24)
  line L7 (4, -24) -> (7.5, -24)
  arc A2 (7.5, -24) -> (7.5, -21) centre (7.5, -22.5) ccw
  line L8 (7.5, -21) -> (4, -21)
  line L9 (4, -21) -> (4, 4.3126)
  circle A3 centre (7.5, -22.5) radius 1.35
  circle A4 centre (3.5, 5) radius 0.85
  circle A5 centre (7.5, -22.5) radius 1.35
extrude "Extrusion16" [suppressed]
named bodies: "Standplatte", "Lehne", "Feststeller"
